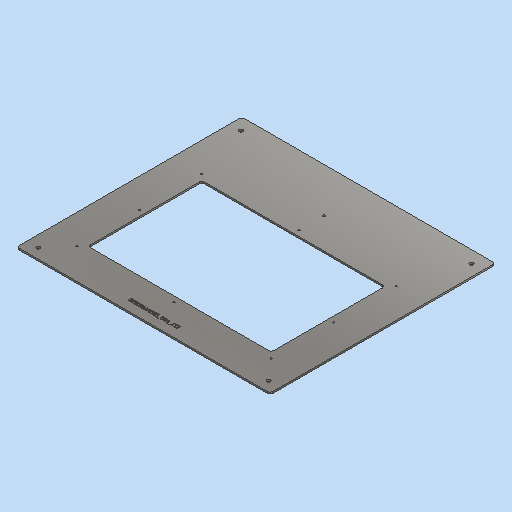
# Autodesk Inventor part: SE0001AN020_G09_112
Saved by Autodesk Inventor 2023.3 (Build 273359000, 359)
## iProperties
Part Number: SE0001AN020_G09_112
Material: Stahl, galvanisiert
Description: =<RBPARTNOTITLE2>
Document SubType Name: Modeling
Designer: Benutzer
Mass: 2750.28 g
Surface Area: 2425.12 cm^2
Volume: 350.354 cm^3
Density: 7.85 g/cm^3
Appearance: Galvanisiert
RBDOCUMENTTYPE: DRF
RBDOCUMENTVERSION: 00
RBDRAWINGMAINSCALE: 1:1
RBDRAWINGMISSINGSPEC: --
RBDRAWINGVOLUME: --
RBGBEDGESIN1: +0,5
RBGBEDGESIN2: +0,2
RBGBEDGESOUT1: -0,3
RBGBEDGESOUT2: -0,1
RBMATERIAL: =<Material>
RBMATMEETS: --
RBMATNO: =<Part Number>
RBPARTMADEOF: 3 x 405 x 456 (FM)
RBPARTNO: SIEHE MNR
RBPARTNOTITLE1: Leo.org
RBPARTNOTITLE2: Abdeckplatte für Kabeldurchführung
RBPARTSAFETYINDICATOR: --
RBSURFACE: Leo.org
RBSURFACE2: Vorverzinktes Blech verwenden
RBZEDGESNORM: ISO13715:2002-06
RBZGENDIMCLASS: m
RBZGENDIMNORM: ISO 2768-1:1989-11
RBZGENGEOCLASS: H
RBZGENGEONORM: ISO 2768-2:1989-11
RBZSURFACENORM: ISO13D2:2002-02
RBZTOLERANCENORM: ISO 14405-1:2010-12
RBGBREMARKSINDEX: E
AnP_Material: =<Material>
AnP_TemplVers: 20190222
AnP_Kategorie: 1
MaxAbmaße: 3,003 x 405 x 456 (FM)
Author: Benutzer
Keywords: =<RBPARTMADEOF>
Comments: =<RBSURFACE2>
Revision Number: 01
Autodesk Inventor part; units mm, degrees
ref_plane "XY Plane" through (0, 0, 0) normal (0, 0, 1) x (1, 0, 0)
sketch "durchbruch_han_16" plane through (0, 0, 0) normal (0, 0, 1) x (1, 0, 0)
  line L0 (-18, 43) -> (18, 43)
  line L1 (18, 43) -> (18, -43)
  line L2 (18, -43) -> (-18, -43)
  line L3 (-18, -43) -> (-18, 43)
  line L4 (0, 43) -> (0, -43) construction
  line L5 (18, 0) -> (-18, 0) construction
  point P0 (0, 0)
  point P1 (-16, 51.5)
  point P2 (16, 51.5)
  point P3 (16, -51.5)
  point P4 (-16, -51.5)
  dimension "d4" = 36
  dimension "d5" = 86
  dimension "d6" = 103
  dimension "d7" = 32
  measures "d4" distance of L1.end L2.end
  measures "d5" distance of L0.end L1.end
  measures "d6" distance of point (-16, -51.5) point (-16, 51.5)
  measures "d7" distance of point (16, 51.5) point (-16, 51.5)
sketch "durchbruch_han_24" plane through (0, 0, 0) normal (0, 0, 1) x (1, 0, 0)
  line L0 (775.149, -6.3606) -> (811.149, -6.3606)
  line L1 (811.149, -6.3606) -> (811.149, 105.6394)
  line L2 (811.149, 105.6394) -> (775.149, 105.6394)
  line L3 (775.149, 105.6394) -> (775.149, -6.3606)
  line L4 (793.149, 105.6394) -> (793.149, -6.3606) construction
  line L5 (775.149, 49.6394) -> (811.149, 49.6394) construction
  point P0 (793.149, 49.6394)
  point P1 (777.149, 114.6394)
  point P2 (809.149, 114.6394)
  point P3 (809.149, -15.3606)
  point P4 (777.149, -15.3606)
  dimension "d8" = 36
  dimension "d9" = 112
  dimension "d10" = 32
  dimension "d11" = 130
  dimension "d12" = 56
  measures "d8" distance of L2.end L1.end
  measures "d9" distance of L1.end L0.end
  measures "d10" distance of point (809.149, 114.639) point (777.149, 114.639)
  measures "d11" distance of point (777.149, -15.361) point (777.149, 114.639)
  measures "d12" distance between parallel lines of L2 L5
sketch "Skizze1" plane through (0, 0, 0) normal (0, 0, 1) x (1, 0, 0)
  line L0 (0, 0) -> (456, 0)
  line L1 (456, 0) -> (456, 405)
  line L2 (456, 405) -> (0, 405)
  line L3 (0, 405) -> (0, 0)
  line L4 (228, 405) -> (228, 0) construction
  line L5 (0, 202.5) -> (456, 202.5) construction
  dimension "d0" = 456
  dimension "d1" = 405
  constraints: 12 end point, 4 midpoint, 2 parallel, 1 horizontal, 1 perpendicular
  measures "d0" distance of L2.end L1.end
  measures "d1" distance of L1.end L0.end
extrude "Extrusion1" add sketch "Skizze1" along normal blind 3
sketch "Skizze_Komponentenanordnung" plane through (0, 0, 3) normal (0, 0, 1) x (1, 0, 0)
  line L0 (0, 0) -> (456, 0) projected
  line L1 (0, 405) -> (0, 0) projected
  line L2 (456, 0) -> (456, 405) projected
  line L3 (456, 405) -> (0, 405) projected
  line L4 (228, 405) -> (228, 0) construction
  line L5 (456, 202.5) -> (0, 202.5) construction
  line L6 (63, 270) -> (393, 270)
  line L7 (393, 270) -> (393, 65)
  line L8 (393, 65) -> (63, 65)
  line L9 (63, 65) -> (63, 270)
  line L10 (410.5, 44.9) -> (45.5, 44.9) construction
  line L11 (45.5, 44.9) -> (45.5, 359.9) construction
  line L12 (45.5, 359.9) -> (410.5, 359.9) construction
  line L13 (410.5, 359.9) -> (410.5, 44.9) construction
  point P0 (228, 202.5)
  point P1 (20.5, 383)
  point P2 (435.5, 383)
  point P3 (435.5, 18)
  point P4 (20.5, 18)
  point P5 (53, 280)
  point P6 (53, 167.5)
  point P7 (53, 55)
  point P8 (228, 280)
  point P9 (228, 55)
  point P10 (403, 280)
  point P11 (403, 167.5)
  point P12 (403, 55)
  point P13 (228, 325)
  dimension "d25" = 456
  dimension "d29" = 405
  dimension "d42" = 415
  dimension "d43" = 365
  dimension "d52" = 330
  dimension "d53" = 205
  dimension "d54" = 63
  dimension "d55" = 65
  dimension "d59" = 55
  dimension "d60" = 165
  dimension "d62" = 350
  dimension "d63" = 53
  dimension "d64" = 102.5
  dimension "d65" = 225
  dimension "d76" = 365
  dimension "d77" = 315
  dimension "d78" = 44.9
  dimension "d79" = 80
  dimension "d88" = 18
  constraints: 20 end point, 8 vertical alignment, 7 horizontal alignment, 6 midpoint, 4 parallel, 2 horizontal, 2 perpendicular, 1 symmetric about line, 1 other
  measures "d25" distance of L0.start L0.end
  measures "d29" distance of L0.end L2.end
  measures "d42" distance of point (435.5, 383) point (20.5, 383)
  measures "d43" distance of point (435.5, 18) point (435.5, 383)
  measures "d52" distance of L7.end L8.end
  measures "d53" distance between parallel lines of L8 L6
  measures "d54" distance between parallel lines of L7 L2
  measures "d55" distance between parallel lines of L0 L8
  measures "d59" distance from line of point (53, 55) L0
  measures "d60" distance from line of point (228, 280) L7
  measures "d62" distance of point (53, 167.5) point (403, 167.5)
  measures "d63" distance from line of point (403, 167.5) L2
  measures "d64" distance from line of point (53, 167.5) L8
  measures "d65" distance of point (53, 280) point (53, 55)
  measures "d76" distance of L12.end L11.end
  measures "d77" distance of L11.end L10.end
  measures "d78" distance between parallel lines of L10 L0
  measures "d79" distance from line of point (228, 325) L3
  measures "d88" distance from line of point (435.5, 18) L0
hole "Bohrung3" at (20.5, 383, 3) at (435.5, 383, 3) at (435.5, 18, 3) at (20.5, 18, 3) direction (0, 0, -1) diameter 7 end through all
fillet "Rundung1" radius 5 4 edges at (0, 0, 1.5) (456, 0, 1.5) (456, 405, 1.5) (0, 405, 1.5)
ref_plane "Arbeitsebene1" through (228, 405, 3) normal (1, 0, 0) x (0, 1, 0)
ref_plane "Arbeitsebene2" through (0, 202.5, 3) normal (0, 1, 0) x (-1, 0, 0)
extrude "Extrusion3" cut sketch "Skizze_Komponentenanordnung" against normal through all contours L6 L7 L8 L9
hole "Bohrung4" at (228, 202.5, 3) at (53, 280, 3) at (53, 167.5, 3) at (53, 55, 3) at (228, 280, 3) at (228, 55, 3) at (403, 280, 3) at (403, 167.5, 3) at (403, 55, 3) direction (0, 0, -1) diameter 3.242 end through all thread size "M4x0.7" designation "M4" class "6H" standard "ISO Metric profile"
hole "Bohrung5" at (228, 325, 3) direction (0, 0, -1) diameter 4.917 end through all thread size "M6x1" designation "M6" class "6H" standard "ISO Metric profile"
sketch "Skizze3" plane through (0, 0, 3) normal (0, 0, 1) x (1, 0, 0)
  line L0 (183, 23) -> (273, 23) construction
  line L1 (273, 23) -> (273, 15) construction
  line L2 (273, 15) -> (183, 15) construction
  line L3 (183, 15) -> (183, 23) construction
  line L4 (5, 0) -> (451, 0) projected
  spline S0 degree 2 poles (185.3184, 16.6627) (184.656, 16.6627) (183.7267, 16.9395) (183.3164, 17.1373) knots 0 0 0 1 2 2 2
  line L5 (183.3164, 17.1373) -> (183.3164, 18.1556)
  line L6 (183.3164, 18.1556) -> (183.3757, 18.1556)
  spline S1 degree 2 poles (183.3757, 18.1556) (183.7761, 17.7799) (184.7895, 17.3647) (185.2591, 17.3647) knots 0 0 0 1 2 2 2
  spline S2 degree 2 poles (185.2591, 17.3647) (185.9314, 17.3647) (186.6185, 17.9233) (186.6185, 18.383) knots 0 0 0 1 2 2 2
  spline S3 degree 2 poles (186.6185, 18.383) (186.6185, 18.7488) (186.2576, 19.2036) (185.8671, 19.3173) knots 0 0 0 1 2 2 2
  spline S4 degree 2 poles (185.8671, 19.3173) (185.5853, 19.3964) (185.1157, 19.5051) (184.7647, 19.5941) knots 0 0 0 1 2 2 2
  spline S5 degree 2 poles (184.7647, 19.5941) (184.4484, 19.6781) (183.9491, 19.9302) (183.7563, 20.1329) knots 0 0 0 1 2 2 2
  spline S6 degree 2 poles (183.7563, 20.1329) (183.5685, 20.3356) (183.3609, 20.8793) (183.3609, 21.2353) knots 0 0 0 1 2 2 2
  spline S7 degree 2 poles (183.3609, 21.2353) (183.3609, 21.9767) (184.5176, 22.9802) (185.4123, 22.9802) knots 0 0 0 1 2 2 2
  spline S8 degree 2 poles (185.4123, 22.9802) (185.9264, 22.9802) (186.836, 22.7776) (187.2265, 22.5848) knots 0 0 0 1 2 2 2
  line L7 (187.2265, 22.5848) -> (187.2265, 21.6159)
  line L8 (187.2265, 21.6159) -> (187.1672, 21.6159)
  spline S9 degree 2 poles (187.1672, 21.6159) (186.8755, 21.8828) (185.966, 22.2783) (185.4667, 22.2783) knots 0 0 0 1 2 2 2
  spline S10 degree 2 poles (185.4667, 22.2783) (184.9032, 22.2783) (184.2062, 21.7494) (184.2062, 21.3193) knots 0 0 0 1 2 2 2
  spline S11 degree 2 poles (184.2062, 21.3193) (184.2062, 20.9337) (184.6165, 20.474) (185.002, 20.3702) knots 0 0 0 1 2 2 2
  spline S12 degree 2 poles (185.002, 20.3702) (185.2591, 20.301) (186.0055, 20.123) (186.2527, 20.0489) knots 0 0 0 1 2 2 2
  spline S13 degree 2 poles (186.2527, 20.0489) (186.8805, 19.8561) (187.4638, 19.08) (187.4638, 18.5115) knots 0 0 0 1 2 2 2
  spline S14 degree 2 poles (187.4638, 18.5115) (187.4638, 18.1506) (187.1721, 17.4586) (186.9101, 17.2164) knots 0 0 0 1 2 2 2
  spline S15 degree 2 poles (186.9101, 17.2164) (186.6185, 16.9494) (185.877, 16.6627) (185.3184, 16.6627) knots 0 0 0 1 2 2 2
  line L9 (188.2893, 16.7715) -> (188.2893, 22.8715)
  line L10 (188.2893, 22.8715) -> (192.1055, 22.8715)
  line L11 (192.1055, 22.8715) -> (192.1055, 22.1498)
  line L12 (192.1055, 22.1498) -> (189.1, 22.1498)
  line L13 (189.1, 22.1498) -> (189.1, 20.4789)
  line L14 (189.1, 20.4789) -> (191.9028, 20.4789)
  line L15 (191.9028, 20.4789) -> (191.9028, 19.7572)
  line L16 (191.9028, 19.7572) -> (189.1, 19.7572)
  line L17 (189.1, 19.7572) -> (189.1, 17.4932)
  line L18 (189.1, 17.4932) -> (192.1055, 17.4932)
  line L19 (192.1055, 17.4932) -> (192.1055, 16.7715)
  line L20 (192.1055, 16.7715) -> (188.2893, 16.7715)
  spline S16 degree 2 poles (196.6187, 19.8215) (196.6187, 18.1803) (195.6647, 16.6429) (194.6711, 16.6429) knots 0 0 0 1 2 2 2
  spline S17 degree 2 poles (194.6711, 16.6429) (193.6626, 16.6429) (192.7185, 18.21) (192.7185, 19.8165) knots 0 0 0 1 2 2 2
  spline S18 degree 2 poles (192.7185, 19.8165) (192.7185, 21.4676) (193.6725, 22.9951) (194.6711, 22.9951) knots 0 0 0 1 2 2 2
  spline S19 degree 2 poles (194.6711, 22.9951) (195.6746, 22.9951) (196.6187, 21.4132) (196.6187, 19.8215) knots 0 0 0 1 2 2 2
  spline S20 degree 2 poles (195.5707, 17.9628) (195.6894, 18.2643) (195.7882, 19.1937) (195.7882, 19.8215) knots 0 0 0 1 2 2 2
  spline S21 degree 2 poles (195.7882, 19.8215) (195.7882, 20.4493) (195.6894, 21.3737) (195.5658, 21.6851) knots 0 0 0 1 2 2 2
  spline S22 degree 2 poles (195.5658, 21.6851) (195.4422, 21.9965) (195.0122, 22.3178) (194.6711, 22.3178) knots 0 0 0 1 2 2 2
  spline S23 degree 2 poles (194.6711, 22.3178) (194.33, 22.3178) (193.89, 21.9965) (193.7615, 21.6752) knots 0 0 0 1 2 2 2
  spline S24 degree 2 poles (193.7615, 21.6752) (193.6379, 21.3638) (193.5489, 20.4147) (193.5489, 19.8165) knots 0 0 0 1 2 2 2
  spline S25 degree 2 poles (193.5489, 19.8165) (193.5489, 19.1739) (193.628, 18.3138) (193.7566, 17.9776) knots 0 0 0 1 2 2 2
  spline S26 degree 2 poles (193.7566, 17.9776) (193.8752, 17.6613) (194.3152, 17.3202) (194.6711, 17.3202) knots 0 0 0 1 2 2 2
  spline S27 degree 2 poles (194.6711, 17.3202) (195.0072, 17.3202) (195.4472, 17.6415) (195.5707, 17.9628) knots 0 0 0 1 2 2 2
  spline S28 degree 2 poles (201.1962, 19.8215) (201.1962, 18.1803) (200.2421, 16.6429) (199.2485, 16.6429) knots 0 0 0 1 2 2 2
  spline S29 degree 2 poles (199.2485, 16.6429) (198.2401, 16.6429) (197.2959, 18.21) (197.2959, 19.8165) knots 0 0 0 1 2 2 2
  spline S30 degree 2 poles (197.2959, 19.8165) (197.2959, 21.4676) (198.25, 22.9951) (199.2485, 22.9951) knots 0 0 0 1 2 2 2
  spline S31 degree 2 poles (199.2485, 22.9951) (200.252, 22.9951) (201.1962, 21.4132) (201.1962, 19.8215) knots 0 0 0 1 2 2 2
  spline S32 degree 2 poles (200.1482, 17.9628) (200.2669, 18.2643) (200.3657, 19.1937) (200.3657, 19.8215) knots 0 0 0 1 2 2 2
  spline S33 degree 2 poles (200.3657, 19.8215) (200.3657, 20.4493) (200.2669, 21.3737) (200.1433, 21.6851) knots 0 0 0 1 2 2 2
  spline S34 degree 2 poles (200.1433, 21.6851) (200.0197, 21.9965) (199.5896, 22.3178) (199.2485, 22.3178) knots 0 0 0 1 2 2 2
  spline S35 degree 2 poles (199.2485, 22.3178) (198.9075, 22.3178) (198.4675, 21.9965) (198.339, 21.6752) knots 0 0 0 1 2 2 2
  spline S36 degree 2 poles (198.339, 21.6752) (198.2154, 21.3638) (198.1264, 20.4147) (198.1264, 19.8165) knots 0 0 0 1 2 2 2
  spline S37 degree 2 poles (198.1264, 19.8165) (198.1264, 19.1739) (198.2055, 18.3138) (198.334, 17.9776) knots 0 0 0 1 2 2 2
  spline S38 degree 2 poles (198.334, 17.9776) (198.4527, 17.6613) (198.8926, 17.3202) (199.2485, 17.3202) knots 0 0 0 1 2 2 2
  spline S39 degree 2 poles (199.2485, 17.3202) (199.5847, 17.3202) (200.0246, 17.6415) (200.1482, 17.9628) knots 0 0 0 1 2 2 2
  spline S40 degree 2 poles (205.7737, 19.8215) (205.7737, 18.1803) (204.8196, 16.6429) (203.826, 16.6429) knots 0 0 0 1 2 2 2
  spline S41 degree 2 poles (203.826, 16.6429) (202.8176, 16.6429) (201.8734, 18.21) (201.8734, 19.8165) knots 0 0 0 1 2 2 2
  spline S42 degree 2 poles (201.8734, 19.8165) (201.8734, 21.4676) (202.8275, 22.9951) (203.826, 22.9951) knots 0 0 0 1 2 2 2
  spline S43 degree 2 poles (203.826, 22.9951) (204.8295, 22.9951) (205.7737, 21.4132) (205.7737, 19.8215) knots 0 0 0 1 2 2 2
  spline S44 degree 2 poles (204.7257, 17.9628) (204.8443, 18.2643) (204.9432, 19.1937) (204.9432, 19.8215) knots 0 0 0 1 2 2 2
  spline S45 degree 2 poles (204.9432, 19.8215) (204.9432, 20.4493) (204.8443, 21.3737) (204.7207, 21.6851) knots 0 0 0 1 2 2 2
  spline S46 degree 2 poles (204.7207, 21.6851) (204.5972, 21.9965) (204.1671, 22.3178) (203.826, 22.3178) knots 0 0 0 1 2 2 2
  spline S47 degree 2 poles (203.826, 22.3178) (203.4849, 22.3178) (203.045, 21.9965) (202.9165, 21.6752) knots 0 0 0 1 2 2 2
  spline S48 degree 2 poles (202.9165, 21.6752) (202.7929, 21.3638) (202.7039, 20.4147) (202.7039, 19.8165) knots 0 0 0 1 2 2 2
  spline S49 degree 2 poles (202.7039, 19.8165) (202.7039, 19.1739) (202.783, 18.3138) (202.9115, 17.9776) knots 0 0 0 1 2 2 2
  spline S50 degree 2 poles (202.9115, 17.9776) (203.0301, 17.6613) (203.4701, 17.3202) (203.826, 17.3202) knots 0 0 0 1 2 2 2
  spline S51 degree 2 poles (203.826, 17.3202) (204.1622, 17.3202) (204.6021, 17.6415) (204.7257, 17.9628) knots 0 0 0 1 2 2 2
  line L21 (210.01, 16.7715) -> (207.0342, 16.7715)
  line L22 (207.0342, 16.7715) -> (207.0342, 17.3943)
  line L23 (207.0342, 17.3943) -> (208.1415, 17.3943)
  line L24 (208.1415, 17.3943) -> (208.1415, 21.4824)
  line L25 (208.1415, 21.4824) -> (207.0342, 21.4824)
  line L26 (207.0342, 21.4824) -> (207.0342, 22.041)
  spline S52 degree 2 poles (207.0342, 22.041) (207.662, 22.041) (208.2552, 22.3969) (208.2947, 22.8912) knots 0 0 0 1 2 2 2
  line L27 (208.2947, 22.8912) -> (208.9275, 22.8912)
  line L28 (208.9275, 22.8912) -> (208.9275, 17.3943)
  line L29 (208.9275, 17.3943) -> (210.01, 17.3943)
  line L30 (210.01, 17.3943) -> (210.01, 16.7715)
  line L31 (210.6477, 16.7715) -> (212.7041, 22.8715)
  line L32 (212.7041, 22.8715) -> (213.7027, 22.8715)
  line L33 (213.7027, 22.8715) -> (215.7591, 16.7715)
  line L34 (215.7591, 16.7715) -> (214.9039, 16.7715)
  line L35 (214.9039, 16.7715) -> (214.3502, 18.4769)
  line L36 (214.3502, 18.4769) -> (212.022, 18.4769)
  line L37 (212.022, 18.4769) -> (211.4683, 16.7715)
  line L38 (211.4683, 16.7715) -> (210.6477, 16.7715)
  line L39 (214.1278, 19.169) -> (213.1836, 22.041)
  line L40 (213.1836, 22.041) -> (212.2444, 19.169)
  line L41 (212.2444, 19.169) -> (214.1278, 19.169)
  line L42 (220.7024, 16.7715) -> (219.7928, 16.7715)
  line L43 (219.7928, 16.7715) -> (217.0938, 22.0311)
  line L44 (217.0938, 22.0311) -> (217.0938, 16.7715)
  line L45 (217.0938, 16.7715) -> (216.3374, 16.7715)
  line L46 (216.3374, 16.7715) -> (216.3374, 22.8715)
  line L47 (216.3374, 22.8715) -> (217.4892, 22.8715)
  line L48 (217.4892, 22.8715) -> (219.946, 18.0419)
  line L49 (219.946, 18.0419) -> (219.946, 22.8715)
  line L50 (219.946, 22.8715) -> (220.7024, 22.8715)
  line L51 (220.7024, 22.8715) -> (220.7024, 16.7715)
  spline S53 degree 2 poles (225.5616, 19.8215) (225.5616, 18.1803) (224.6075, 16.6429) (223.6139, 16.6429) knots 0 0 0 1 2 2 2
  spline S54 degree 2 poles (223.6139, 16.6429) (222.6055, 16.6429) (221.6613, 18.21) (221.6613, 19.8165) knots 0 0 0 1 2 2 2
  spline S55 degree 2 poles (221.6613, 19.8165) (221.6613, 21.4676) (222.6154, 22.9951) (223.6139, 22.9951) knots 0 0 0 1 2 2 2
  spline S56 degree 2 poles (223.6139, 22.9951) (224.6174, 22.9951) (225.5616, 21.4132) (225.5616, 19.8215) knots 0 0 0 1 2 2 2
  spline S57 degree 2 poles (224.5136, 17.9628) (224.6323, 18.2643) (224.7311, 19.1937) (224.7311, 19.8215) knots 0 0 0 1 2 2 2
  spline S58 degree 2 poles (224.7311, 19.8215) (224.7311, 20.4493) (224.6323, 21.3737) (224.5087, 21.6851) knots 0 0 0 1 2 2 2
  spline S59 degree 2 poles (224.5087, 21.6851) (224.3851, 21.9965) (223.955, 22.3178) (223.6139, 22.3178) knots 0 0 0 1 2 2 2
  spline S60 degree 2 poles (223.6139, 22.3178) (223.2729, 22.3178) (222.8329, 21.9965) (222.7044, 21.6752) knots 0 0 0 1 2 2 2
  spline S61 degree 2 poles (222.7044, 21.6752) (222.5808, 21.3638) (222.4918, 20.4147) (222.4918, 19.8165) knots 0 0 0 1 2 2 2
  spline S62 degree 2 poles (222.4918, 19.8165) (222.4918, 19.1739) (222.5709, 18.3138) (222.6994, 17.9776) knots 0 0 0 1 2 2 2
  spline S63 degree 2 poles (222.6994, 17.9776) (222.8181, 17.6613) (223.258, 17.3202) (223.6139, 17.3202) knots 0 0 0 1 2 2 2
  spline S64 degree 2 poles (223.6139, 17.3202) (223.9501, 17.3202) (224.39, 17.6415) (224.5136, 17.9628) knots 0 0 0 1 2 2 2
  line L52 (230.1045, 16.7715) -> (226.3426, 16.7715)
  line L53 (226.3426, 16.7715) -> (226.3426, 17.6365)
  spline S65 degree 2 poles (226.3426, 17.6365) (226.748, 18.0172) (227.4697, 18.7241) (227.8157, 19.1047) knots 0 0 0 1 2 2 2
  spline S66 degree 2 poles (227.8157, 19.1047) (228.5127, 19.8709) (229.0219, 20.7904) (229.0219, 21.2797) knots 0 0 0 1 2 2 2
  spline S67 degree 2 poles (229.0219, 21.2797) (229.0219, 21.5368) (228.8637, 21.9224) (228.7203, 22.0459) knots 0 0 0 1 2 2 2
  spline S68 degree 2 poles (228.7203, 22.0459) (228.577, 22.1695) (228.2013, 22.2931) (227.9739, 22.2931) knots 0 0 0 1 2 2 2
  spline S69 degree 2 poles (227.9739, 22.2931) (227.7564, 22.2931) (227.3115, 22.1844) (227.1088, 22.1003) knots 0 0 0 1 2 2 2
  spline S70 degree 2 poles (227.1088, 22.1003) (226.9358, 22.0311) (226.6145, 21.8334) (226.5156, 21.7642) knots 0 0 0 1 2 2 2
  line L54 (226.5156, 21.7642) -> (226.4712, 21.7642)
  line L55 (226.4712, 21.7642) -> (226.4712, 22.6342)
  spline S71 degree 2 poles (226.4712, 22.6342) (226.7233, 22.7578) (227.6279, 23) (228.0332, 23) knots 0 0 0 1 2 2 2
  spline S72 degree 2 poles (228.0332, 23) (228.8884, 23) (229.8524, 22.0954) (229.8524, 21.3242) knots 0 0 0 1 2 2 2
  spline S73 degree 2 poles (229.8524, 21.3242) (229.8524, 20.9634) (229.6843, 20.3603) (229.536, 20.1032) knots 0 0 0 1 2 2 2
  spline S74 degree 2 poles (229.536, 20.1032) (229.3877, 19.8363) (228.9576, 19.3123) (228.7203, 19.0602) knots 0 0 0 1 2 2 2
  spline S75 degree 2 poles (228.7203, 19.0602) (228.3348, 18.64) (227.3906, 17.7404) (227.1088, 17.4784) knots 0 0 0 1 2 2 2
  line L56 (227.1088, 17.4784) -> (230.1045, 17.4784)
  line L57 (230.1045, 17.4784) -> (230.1045, 16.7715)
  spline S76 degree 2 poles (234.7165, 19.8215) (234.7165, 18.1803) (233.7625, 16.6429) (232.7689, 16.6429) knots 0 0 0 1 2 2 2
  spline S77 degree 2 poles (232.7689, 16.6429) (231.7605, 16.6429) (230.8163, 18.21) (230.8163, 19.8165) knots 0 0 0 1 2 2 2
  spline S78 degree 2 poles (230.8163, 19.8165) (230.8163, 21.4676) (231.7703, 22.9951) (232.7689, 22.9951) knots 0 0 0 1 2 2 2
  spline S79 degree 2 poles (232.7689, 22.9951) (233.7724, 22.9951) (234.7165, 21.4132) (234.7165, 19.8215) knots 0 0 0 1 2 2 2
  spline S80 degree 2 poles (233.6686, 17.9628) (233.7872, 18.2643) (233.8861, 19.1937) (233.8861, 19.8215) knots 0 0 0 1 2 2 2
  spline S81 degree 2 poles (233.8861, 19.8215) (233.8861, 20.4493) (233.7872, 21.3737) (233.6636, 21.6851) knots 0 0 0 1 2 2 2
  spline S82 degree 2 poles (233.6636, 21.6851) (233.54, 21.9965) (233.11, 22.3178) (232.7689, 22.3178) knots 0 0 0 1 2 2 2
  spline S83 degree 2 poles (232.7689, 22.3178) (232.4278, 22.3178) (231.9878, 21.9965) (231.8593, 21.6752) knots 0 0 0 1 2 2 2
  spline S84 degree 2 poles (231.8593, 21.6752) (231.7357, 21.3638) (231.6468, 20.4147) (231.6468, 19.8165) knots 0 0 0 1 2 2 2
  spline S85 degree 2 poles (231.6468, 19.8165) (231.6468, 19.1739) (231.7259, 18.3138) (231.8544, 17.9776) knots 0 0 0 1 2 2 2
  spline S86 degree 2 poles (231.8544, 17.9776) (231.973, 17.6613) (232.413, 17.3202) (232.7689, 17.3202) knots 0 0 0 1 2 2 2
  spline S87 degree 2 poles (232.7689, 17.3202) (233.105, 17.3202) (233.545, 17.6415) (233.6686, 17.9628) knots 0 0 0 1 2 2 2
  line L58 (239.6944, 15.5455) -> (234.9884, 15.5455)
  line L59 (234.9884, 15.5455) -> (234.9884, 16.0745)
  line L60 (234.9884, 16.0745) -> (239.6944, 16.0745)
  line L61 (239.6944, 16.0745) -> (239.6944, 15.5455)
  spline S88 degree 2 poles (242.8037, 16.6528) (242.1562, 16.6528) (241.0835, 17.0483) (240.6979, 17.4487) knots 0 0 0 1 2 2 2
  spline S89 degree 2 poles (240.6979, 17.4487) (240.3123, 17.8541) (239.902, 19.0503) (239.902, 19.8264) knots 0 0 0 1 2 2 2
  spline S90 degree 2 poles (239.902, 19.8264) (239.902, 20.563) (240.3173, 21.7296) (240.7028, 22.1448) knots 0 0 0 1 2 2 2
  spline S91 degree 2 poles (240.7028, 22.1448) (241.0736, 22.5452) (242.1611, 22.9802) (242.8087, 22.9802) knots 0 0 0 1 2 2 2
  spline S92 degree 2 poles (242.8087, 22.9802) (243.1201, 22.9802) (243.6836, 22.8912) (243.9407, 22.8122) knots 0 0 0 1 2 2 2
  spline S93 degree 2 poles (243.9407, 22.8122) (244.1483, 22.7528) (244.6525, 22.5353) (244.8058, 22.4562) knots 0 0 0 1 2 2 2
  line L62 (244.8058, 22.4562) -> (244.8058, 21.4775)
  line L63 (244.8058, 21.4775) -> (244.7365, 21.4775)
  spline S94 degree 2 poles (244.7365, 21.4775) (244.5833, 21.6109) (244.262, 21.8532) (243.9654, 21.9916) knots 0 0 0 1 2 2 2
  spline S95 degree 2 poles (243.9654, 21.9916) (243.7182, 22.1152) (243.0806, 22.2783) (242.7148, 22.2783) knots 0 0 0 1 2 2 2
  spline S96 degree 2 poles (242.7148, 22.2783) (241.8348, 22.2783) (240.7473, 20.9535) (240.7473, 19.8511) knots 0 0 0 1 2 2 2
  spline S97 degree 2 poles (240.7473, 19.8511) (240.7473, 19.2382) (241.034, 18.3187) (241.3059, 18.0024) knots 0 0 0 1 2 2 2
  spline S98 degree 2 poles (241.3059, 18.0024) (241.5679, 17.686) (242.3094, 17.3548) (242.7741, 17.3548) knots 0 0 0 1 2 2 2
  spline S99 degree 2 poles (242.7741, 17.3548) (243.1152, 17.3548) (243.7973, 17.4536) (244.0297, 17.5525) knots 0 0 0 1 2 2 2
  line L64 (244.0297, 17.5525) -> (244.0297, 19.1294)
  line L65 (244.0297, 19.1294) -> (242.6159, 19.1294)
  line L66 (242.6159, 19.1294) -> (242.6159, 19.8412)
  line L67 (242.6159, 19.8412) -> (244.8305, 19.8412)
  line L68 (244.8305, 19.8412) -> (244.8305, 17.1768)
  spline S100 degree 2 poles (244.8305, 17.1768) (244.6772, 17.1076) (244.1532, 16.8951) (243.9308, 16.8308) knots 0 0 0 1 2 2 2
  spline S101 degree 2 poles (243.9308, 16.8308) (243.6293, 16.7418) (243.1448, 16.6528) (242.8037, 16.6528) knots 0 0 0 1 2 2 2
  spline S102 degree 2 poles (249.4722, 19.8215) (249.4722, 18.1803) (248.5182, 16.6429) (247.5246, 16.6429) knots 0 0 0 1 2 2 2
  spline S103 degree 2 poles (247.5246, 16.6429) (246.5161, 16.6429) (245.572, 18.21) (245.572, 19.8165) knots 0 0 0 1 2 2 2
  spline S104 degree 2 poles (245.572, 19.8165) (245.572, 21.4676) (246.526, 22.9951) (247.5246, 22.9951) knots 0 0 0 1 2 2 2
  spline S105 degree 2 poles (247.5246, 22.9951) (248.528, 22.9951) (249.4722, 21.4132) (249.4722, 19.8215) knots 0 0 0 1 2 2 2
  spline S106 degree 2 poles (248.4242, 17.9628) (248.5429, 18.2643) (248.6417, 19.1937) (248.6417, 19.8215) knots 0 0 0 1 2 2 2
  spline S107 degree 2 poles (248.6417, 19.8215) (248.6417, 20.4493) (248.5429, 21.3737) (248.4193, 21.6851) knots 0 0 0 1 2 2 2
  spline S108 degree 2 poles (248.4193, 21.6851) (248.2957, 21.9965) (247.8656, 22.3178) (247.5246, 22.3178) knots 0 0 0 1 2 2 2
  spline S109 degree 2 poles (247.5246, 22.3178) (247.1835, 22.3178) (246.7435, 21.9965) (246.615, 21.6752) knots 0 0 0 1 2 2 2
  spline S110 degree 2 poles (246.615, 21.6752) (246.4914, 21.3638) (246.4024, 20.4147) (246.4024, 19.8165) knots 0 0 0 1 2 2 2
  spline S111 degree 2 poles (246.4024, 19.8165) (246.4024, 19.1739) (246.4815, 18.3138) (246.6101, 17.9776) knots 0 0 0 1 2 2 2
  spline S112 degree 2 poles (246.6101, 17.9776) (246.7287, 17.6613) (247.1686, 17.3202) (247.5246, 17.3202) knots 0 0 0 1 2 2 2
  spline S113 degree 2 poles (247.5246, 17.3202) (247.8607, 17.3202) (248.3006, 17.6415) (248.4242, 17.9628) knots 0 0 0 1 2 2 2
  spline S114 degree 2 poles (250.0852, 20.8892) (250.0852, 21.3588) (250.3917, 22.1399) (250.6586, 22.4216) knots 0 0 0 1 2 2 2
  spline S115 degree 2 poles (250.6586, 22.4216) (250.9107, 22.6935) (251.6472, 22.9951) (252.0229, 22.9951) knots 0 0 0 1 2 2 2
  spline S116 degree 2 poles (252.0229, 22.9951) (252.4431, 22.9951) (253.1253, 22.7133) (253.3774, 22.4464) knots 0 0 0 1 2 2 2
  spline S117 degree 2 poles (253.3774, 22.4464) (253.6938, 22.1102) (254.0398, 21.0227) (254.0398, 20.1873) knots 0 0 0 1 2 2 2
  spline S118 degree 2 poles (254.0398, 20.1873) (254.0398, 19.431) (253.6987, 18.0765) (253.3675, 17.6267) knots 0 0 0 1 2 2 2
  spline S119 degree 2 poles (253.3675, 17.6267) (253.0165, 17.1521) (252.0279, 16.6528) (251.3062, 16.6528) knots 0 0 0 1 2 2 2
  spline S120 degree 2 poles (251.3062, 16.6528) (251.143, 16.6528) (250.7723, 16.6874) (250.6141, 16.7369) knots 0 0 0 1 2 2 2
  line L69 (250.6141, 16.7369) -> (250.6141, 17.5229)
  line L70 (250.6141, 17.5229) -> (250.6536, 17.5229)
  spline S121 degree 2 poles (250.6536, 17.5229) (250.7575, 17.4635) (251.1925, 17.3597) (251.4149, 17.3597) knots 0 0 0 1 2 2 2
  spline S122 degree 2 poles (251.4149, 17.3597) (252.2157, 17.3597) (253.1302, 18.4176) (253.1945, 19.3964) knots 0 0 0 1 2 2 2
  spline S123 degree 2 poles (253.1945, 19.3964) (252.8682, 19.1739) (252.275, 18.9712) (251.9241, 18.9712) knots 0 0 0 1 2 2 2
  spline S124 degree 2 poles (251.9241, 18.9712) (251.5879, 18.9712) (251.0293, 19.1195) (250.7476, 19.3321) knots 0 0 0 1 2 2 2
  spline S125 degree 2 poles (250.7476, 19.3321) (250.4213, 19.5842) (250.0852, 20.3504) (250.0852, 20.8892) knots 0 0 0 1 2 2 2
  spline S126 degree 2 poles (253.2143, 20.3702) (253.2143, 20.9881) (252.9869, 21.7691) (252.7842, 21.9817) knots 0 0 0 1 2 2 2
  spline S127 degree 2 poles (252.7842, 21.9817) (252.6062, 22.1794) (252.2355, 22.3277) (252.018, 22.3277) knots 0 0 0 1 2 2 2
  spline S128 degree 2 poles (252.018, 22.3277) (251.5138, 22.3277) (250.9156, 21.606) (250.9156, 20.9238) knots 0 0 0 1 2 2 2
  spline S129 degree 2 poles (250.9156, 20.9238) (250.9156, 20.5382) (251.1134, 20.039) (251.3309, 19.861) knots 0 0 0 1 2 2 2
  spline S130 degree 2 poles (251.3309, 19.861) (251.4891, 19.7325) (251.8796, 19.6485) (252.107, 19.6485) knots 0 0 0 1 2 2 2
  spline S131 degree 2 poles (252.107, 19.6485) (252.369, 19.6485) (252.972, 19.8314) (253.1994, 19.9846) knots 0 0 0 1 2 2 2
  spline S132 degree 2 poles (253.1994, 19.9846) (253.2044, 20.0439) (253.2143, 20.2466) (253.2143, 20.3702) knots 0 0 0 1 2 2 2
  line L71 (259.0276, 15.5455) -> (254.3216, 15.5455)
  line L72 (254.3216, 15.5455) -> (254.3216, 16.0745)
  line L73 (254.3216, 16.0745) -> (259.0276, 16.0745)
  line L74 (259.0276, 16.0745) -> (259.0276, 15.5455)
  line L75 (262.8635, 16.7715) -> (259.8877, 16.7715)
  line L76 (259.8877, 16.7715) -> (259.8877, 17.3943)
  line L77 (259.8877, 17.3943) -> (260.995, 17.3943)
  line L78 (260.995, 17.3943) -> (260.995, 21.4824)
  line L79 (260.995, 21.4824) -> (259.8877, 21.4824)
  line L80 (259.8877, 21.4824) -> (259.8877, 22.041)
  spline S133 degree 2 poles (259.8877, 22.041) (260.5155, 22.041) (261.1087, 22.3969) (261.1482, 22.8912) knots 0 0 0 1 2 2 2
  line L81 (261.1482, 22.8912) -> (261.781, 22.8912)
  line L82 (261.781, 22.8912) -> (261.781, 17.3943)
  line L83 (261.781, 17.3943) -> (262.8635, 17.3943)
  line L84 (262.8635, 17.3943) -> (262.8635, 16.7715)
  line L85 (267.441, 16.7715) -> (264.4652, 16.7715)
  line L86 (264.4652, 16.7715) -> (264.4652, 17.3943)
  line L87 (264.4652, 17.3943) -> (265.5724, 17.3943)
  line L88 (265.5724, 17.3943) -> (265.5724, 21.4824)
  line L89 (265.5724, 21.4824) -> (264.4652, 21.4824)
  line L90 (264.4652, 21.4824) -> (264.4652, 22.041)
  spline S134 degree 2 poles (264.4652, 22.041) (265.093, 22.041) (265.6861, 22.3969) (265.7257, 22.8912) knots 0 0 0 1 2 2 2
  line L91 (265.7257, 22.8912) -> (266.3584, 22.8912)
  line L92 (266.3584, 22.8912) -> (266.3584, 17.3943)
  line L93 (266.3584, 17.3943) -> (267.441, 17.3943)
  line L94 (267.441, 17.3943) -> (267.441, 16.7715)
  line L95 (272.325, 16.7715) -> (268.5631, 16.7715)
  line L96 (268.5631, 16.7715) -> (268.5631, 17.6365)
  spline S135 degree 2 poles (268.5631, 17.6365) (268.9685, 18.0172) (269.6902, 18.7241) (270.0362, 19.1047) knots 0 0 0 1 2 2 2
  spline S136 degree 2 poles (270.0362, 19.1047) (270.7332, 19.8709) (271.2424, 20.7904) (271.2424, 21.2797) knots 0 0 0 1 2 2 2
  spline S137 degree 2 poles (271.2424, 21.2797) (271.2424, 21.5368) (271.0842, 21.9224) (270.9408, 22.0459) knots 0 0 0 1 2 2 2
  spline S138 degree 2 poles (270.9408, 22.0459) (270.7975, 22.1695) (270.4218, 22.2931) (270.1944, 22.2931) knots 0 0 0 1 2 2 2
  spline S139 degree 2 poles (270.1944, 22.2931) (269.9769, 22.2931) (269.532, 22.1844) (269.3293, 22.1003) knots 0 0 0 1 2 2 2
  spline S140 degree 2 poles (269.3293, 22.1003) (269.1563, 22.0311) (268.835, 21.8334) (268.7361, 21.7642) knots 0 0 0 1 2 2 2
  line L97 (268.7361, 21.7642) -> (268.6917, 21.7642)
  line L98 (268.6917, 21.7642) -> (268.6917, 22.6342)
  spline S141 degree 2 poles (268.6917, 22.6342) (268.9438, 22.7578) (269.8484, 23) (270.2537, 23) knots 0 0 0 1 2 2 2
  spline S142 degree 2 poles (270.2537, 23) (271.1089, 23) (272.0729, 22.0954) (272.0729, 21.3242) knots 0 0 0 1 2 2 2
  spline S143 degree 2 poles (272.0729, 21.3242) (272.0729, 20.9634) (271.9048, 20.3603) (271.7565, 20.1032) knots 0 0 0 1 2 2 2
  spline S144 degree 2 poles (271.7565, 20.1032) (271.6082, 19.8363) (271.1781, 19.3123) (270.9408, 19.0602) knots 0 0 0 1 2 2 2
  spline S145 degree 2 poles (270.9408, 19.0602) (270.5553, 18.64) (269.6111, 17.7404) (269.3293, 17.4784) knots 0 0 0 1 2 2 2
  line L99 (269.3293, 17.4784) -> (272.325, 17.4784)
  line L100 (272.325, 17.4784) -> (272.325, 16.7715)
  point P0 (0, 0)
  point P1 (228, 15)
  point P2 (228, 0)
  dimension "d89" = 15
  dimension "d90" = 8
  dimension "d91" = 90
  constraints: 2 midpoint, 1 vertical alignment, 2 other
  measures "d89" distance between parallel lines of L4 L2
  measures "d90" distance of L2.end L0.start
  measures "d91" distance of L0.start L0.end
emboss "Prägen1" sketch "Skizze3" operation cut depth 0.1 direction (0, 0, -1)
fillet "Rundung2" radius 5 4 edges at (63, 270, 1.5) (63, 65, 1.5) (393, 65, 1.5) (393, 270, 1.5)
equation "\"d60\" = 0.5 * d52"
equation "\"d63\" = -0.5 * d62 + 0.5 * d25"
equation "\"d64\" = 0.5 * d53"
equation "\"d12\" = 0.5 * d9"
equation "\"d54\" = -0.5 * d52 + 0.5 * d25"
